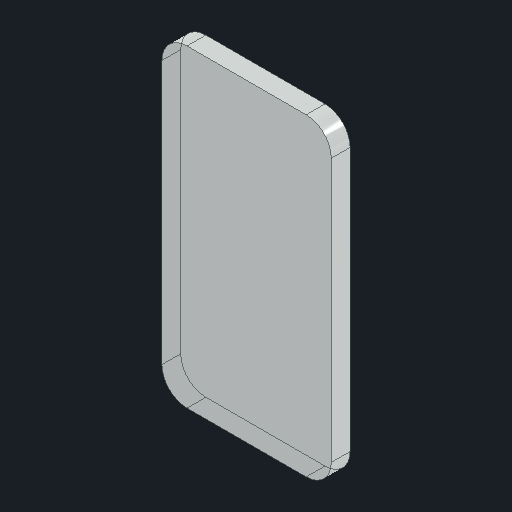
# Autodesk Inventor part: 7_6_3_vitre_cabine
Saved by Autodesk Inventor 2026 (Build 300175000, 175)
## iProperties
Created: 2025-06-22
Part Number: 7_6_3_vitre_cabine
Material: Glass
Document SubType Name: Modeling
Designer: remg9
Density: 2.18 g/cm^3
Appearance: Clear
Author: remg9
Autodesk Inventor part; units mm, degrees
ref_plane "YZ Plane" through (0, 0, 0) normal (1, 0, 0) x (0, 1, 0)
ref_plane "XZ Plane" through (0, 0, 0) normal (0, 1, 0) x (-1, 0, 0)
ref_plane "XY Plane" through (0, 0, 0) normal (0, 0, 1) x (1, 0, 0)
sketch "Sketch1" plane through (0, 0, 0) normal (0, 0, 1) x (1, 0, 0)
  line L0 (-9.5, 0) -> (9.5, 0)
  line L1 (13.5, -4) -> (13.5, -46)
  line L2 (9.5, -50) -> (-9.5, -50)
  line L3 (-13.5, -46) -> (-13.5, -4)
  arc A0 (-13.5, -46) -> (-9.5, -50) centre (-9.5, -46) ccw
  arc A1 (9.5, -50) -> (13.5, -46) centre (9.5, -46) ccw
  arc A2 (13.5, -4) -> (9.5, 0) centre (9.5, -4) ccw
  arc A3 (-9.5, 0) -> (-13.5, -4) centre (-9.5, -4) ccw
  point P0 (0, 0)
  point P1 (0, 0)
  dimension "d2" = 50
  dimension "d3" = 27
  dimension "d4" = 4
  dimension "d5" = 4
  dimension "d6" = 4
  dimension "d7" = 4
  constraints: 8 end point, 8 point on circle, 8 tangent, 4 centre point, 2 parallel, 1 coincident, 1 horizontal, 1 midpoint, 1 perpendicular
  measures "d2" distance between parallel lines of L2 L0
  measures "d3" distance between parallel lines of L3 L1
  measures "d4" radius of A2
  measures "d5" radius of A3
  measures "d6" radius of A1
  measures "d7" radius of A0
extrude "Extrusion1" add sketch "Sketch1" along normal blind 3
body "Solid1"
